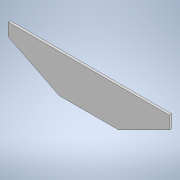
# Autodesk Inventor part: INTARITURA_STG_DR_MID
Saved by Autodesk Inventor 2022.6 (Build 266554000, 554)
## iProperties
Created: 2025-04-03
Part Number: INTARITURA_STG_DR_MID
Material: Generic
Document SubType Name: Modeling
Designer: Dragos Macovei
Density: 1 g/cm^3
Appearance: Default
Author: Dragos Macovei
Autodesk Inventor part; units mm, degrees
ref_plane "YZ Plane" through (0, 0, 0) normal (1, 0, 0) x (0, 1, 0)
ref_plane "XZ Plane" through (0, 0, 0) normal (0, 1, 0) x (-1, 0, 0)
ref_plane "XY Plane" through (0, 0, 0) normal (0, 0, 1) x (1, 0, 0)
sketch "Sketch1" plane through (0, 0, 0) normal (0, 0, 1) x (1, 0, 0)
  line L0 (-400, -50) -> (-864, -50)
  line L1 (-1264, 150) -> (-1264, 250)
  line L2 (-1264, 250) -> (0, 250)
  line L3 (0, 250) -> (0, 150)
  line L4 (-1264, 150) -> (-864, -50)
  line L5 (-400, -50) -> (0, 150)
  line L6 (-1264, 150) -> (0, 150) construction
  point P0 (0, 0)
  dimension "d1" = 1264
  dimension "d2" = 300
  dimension "d3" = 400
  dimension "d4" = 100
  dimension "d5" = 100
  dimension "d8" = 400
  constraints: 14 end point, 2 parallel, 1 horizontal, 1 perpendicular
  measures "d1" distance of L1.start L3.end
  measures "d2" distance between parallel lines of L0 L2
  measures "d3" distance from line of L0.end L1
  measures "d4" distance from line of L1.start L2
  measures "d5" distance from line of L3.end L2
  measures "d8" horizontal distance of L2.end L0.start
extrude "Extrusion1" add sketch "Sketch1" along normal blind 18
equation "\"d5\" = d4"
body "Solid1"
